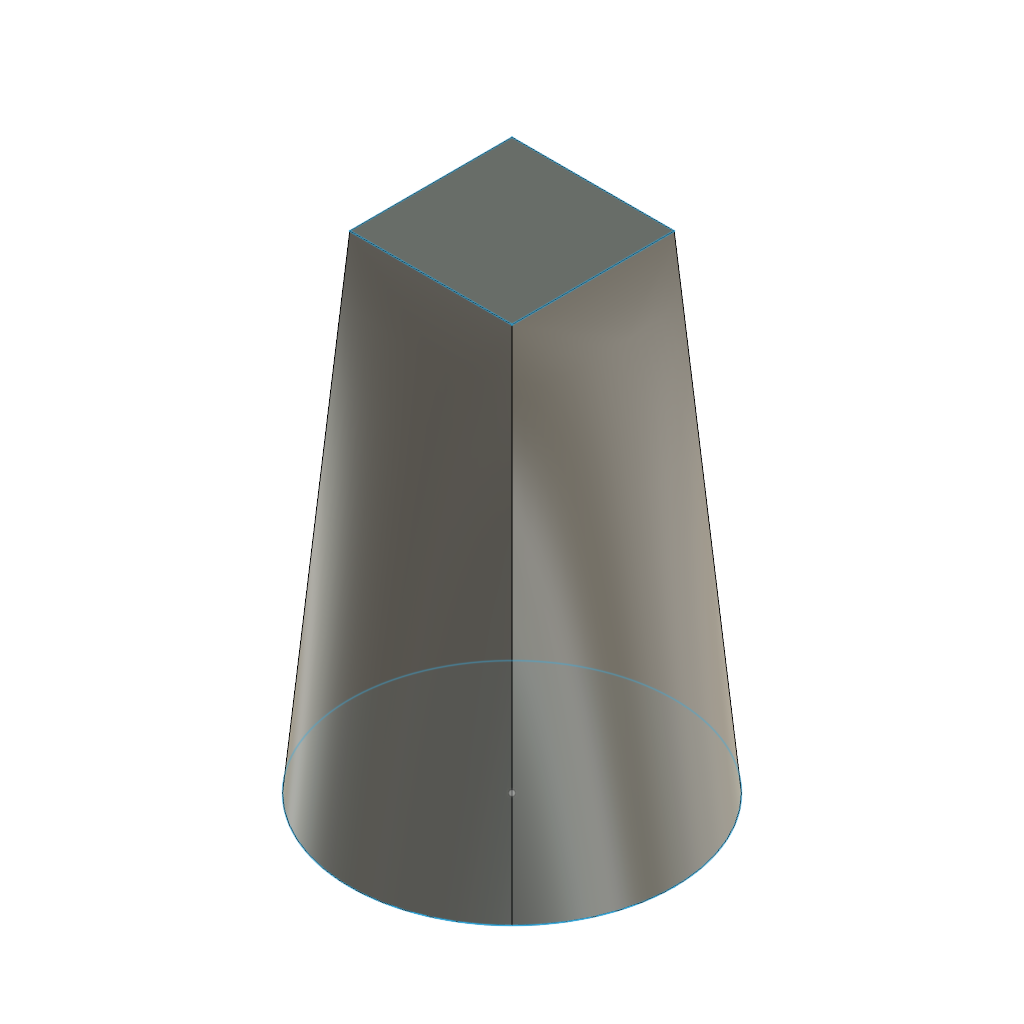
Loft (Autodesk Fusion 360 design; units mm, degrees)
part number: 2026-11-12-11-46-39-710
Autodesk Fusion 360 part; units mm, degrees
sketch "Loft base" plane through (0, 0, 0) normal (0, 0, 1) x (1, 0, 0)
  circle A0 centre (0, 0) radius 10
ref_plane "WorkPlane1" through (0, 0, 30) normal (0, 0, 1) x (1, 0, 0)
sketch "Loft top" plane through (0, 0, 30) normal (0, 0, 1) x (1, 0, 0)
  line L0 (-5, -5) -> (5, -5)
  line L1 (5, -5) -> (5, 5)
  line L2 (5, 5) -> (-5, 5)
  line L3 (-5, 5) -> (-5, -5)
loft "Round to square" add profiles "Loft base", "Loft top" section 1 section 2
